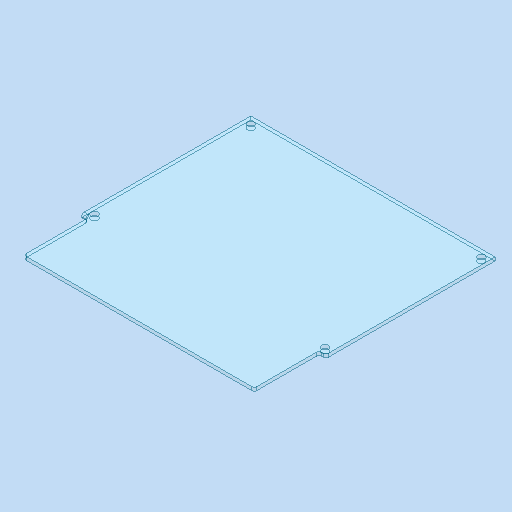
# Autodesk Inventor part: SE0004AN000_G01_111
Saved by Autodesk Inventor 2023.3 (Build 273359000, 359)
## iProperties
Part Number: SE0004AN000_G01_111
Material: Kst - PC (Eslon, klar)
Description: =<RBPARTNOTITLE2>
Document SubType Name: Modeling
Designer: Benutzer
Mass: 361.371 g
Surface Area: 1553.78 cm^2
Volume: 301.143 cm^3
Density: 1.2 g/cm^3
Appearance: Klar AnP
Vendor: Koenig
RBDOCUMENTTYPE: DRF
RBDOCUMENTVERSION: 00
RBDRAWINGMAINSCALE: 1:1
RBDRAWINGMISSINGSPEC: --
RBDRAWINGVOLUME: --
RBGBEDGESIN1: +0,5
RBGBEDGESIN2: +0,2
RBGBEDGESOUT1: -0,3
RBGBEDGESOUT2: -0,1
RBMATERIAL: =<Material>
RBMATMEETS: --
RBMATNO: =<Part Number>
RBPARTMADEOF: 4,005 x 271 x 283 (FM)
RBPARTNO: SIEHE MNR
RBPARTNOTITLE1: manufactured part
RBPARTNOTITLE2: Anfertigungsteil
RBPARTSAFETYINDICATOR: --
RBSURFACE: --
RBSURFACE2: --
RBZEDGESNORM: ISO13715:2002-06
RBZGENDIMCLASS: m
RBZGENDIMNORM: ISO 2768-1:1989-11
RBZGENGEOCLASS: H
RBZGENGEONORM: ISO 2768-2:1989-11
RBZSURFACENORM: ISO13D2:2002-02
RBZTOLERANCENORM: ISO 14405-1:2010-12
AnP_Material: =<Material>
AnP_TemplVers: 20190222
AnP_Kategorie: 1
MaxAbmaße: 4,005 x 271 x 283 (FM)
Author: Benutzer
Keywords: =<RBPARTMADEOF>
Comments: =<RBSURFACE2>
Revision Number: 01
Autodesk Inventor part; units mm, degrees
ref_plane "YZ Plane" through (0, 0, 0) normal (1, 0, 0) x (0, 1, 0)
ref_plane "XZ Plane" through (0, 0, 0) normal (0, 1, 0) x (-1, 0, 0)
ref_plane "XY Plane" through (0, 0, 0) normal (0, 0, 1) x (1, 0, 0)
sketch "Skizze1" plane through (0, 0, 0) normal (0, 0, 1) x (1, 0, 0)
  line L0 (0, 0) -> (283, 0)
  line L1 (283, 0) -> (283, 271)
  line L2 (283, 271) -> (0, 271)
  line L3 (0, 271) -> (0, 0)
  dimension "d0" = 283
  dimension "d1" = 271
  constraints: 8 end point, 2 parallel, 1 horizontal, 1 perpendicular
  measures "d0" distance of L2.end L1.end
  measures "d1" distance of L1.end L0.end
extrude "Extrusion1" add sketch "Skizze1" along normal blind 4
sketch "Skizze2" plane through (0, 0, 4) normal (0, 0, 1) x (1, 0, 0)
  line L0 (0, 271) -> (0, 0) projected
  line L1 (283, 271) -> (0, 271) projected
  line L2 (283, 0) -> (283, 271) projected
  line L3 (0, 0) -> (283, 0) projected
  point P0 (8, 263)
  point P1 (275, 263)
  point P2 (275, 82)
  point P3 (8, 82)
  dimension "d4" = 8
  dimension "d5" = 8
  dimension "d6" = 8
  dimension "d15" = 181
  constraints: 2 horizontal alignment, 2 vertical alignment
  measures "d4" distance from line of L0 point (8, 263)
  measures "d5" distance from line of L1 point (8, 263)
  measures "d6" distance from line of L2 point (275, 263)
  measures "d15" distance of point (275, 82) point (275, 263)
hole "Bohrung1" at (8, 263, 4) at (275, 263, 4) at (275, 82, 4) at (8, 82, 4) direction (0, 0, -1) diameter 8 depth 8 tip angle 118
sketch "Skizze3" plane through (0, 0, 4) normal (0, 0, 1) x (1, 0, 0)
  circle A0 centre (8, 263) radius 4 projected
  circle A1 centre (275, 263) radius 4 projected
  line L0 (0, 0) -> (283, 0) projected
  line L1 (283, 0) -> (283, 271) projected
  line L2 (283, 271) -> (0, 271) projected
  line L3 (0, 271) -> (0, 0) projected
  line L4 (0, 75) -> (8, 75)
  line L5 (8, 75) -> (8, 0)
  line L6 (8, 0) -> (0, 0)
  line L7 (0, 0) -> (0, 75)
  line L8 (283, 75) -> (275, 75)
  line L9 (275, 75) -> (275, 0)
  line L10 (275, 0) -> (283, 0)
  line L11 (283, 0) -> (283, 75)
  dimension "d16" = 75
  dimension "d17" = 8
  dimension "d18" = 8
  constraints: 16 end point, 5 point on line, 4 parallel, 2 horizontal, 2 perpendicular
  measures "d16" distance of L5.end L4.end
  measures "d17" distance between parallel lines of L5 L3
  measures "d18" distance between parallel lines of L1 L9
extrude "Extrusion2" cut sketch "Skizze3" against normal through all contours L3 L4 L5 L0 | L9 L8 L1 L0
fillet "Rundung1" radius 3 6 edges at (275, 0, 2) (283, 75, 2) (8, 0, 2) (8, 75, 2) (4, 75, 4) (275, 75, 2)
